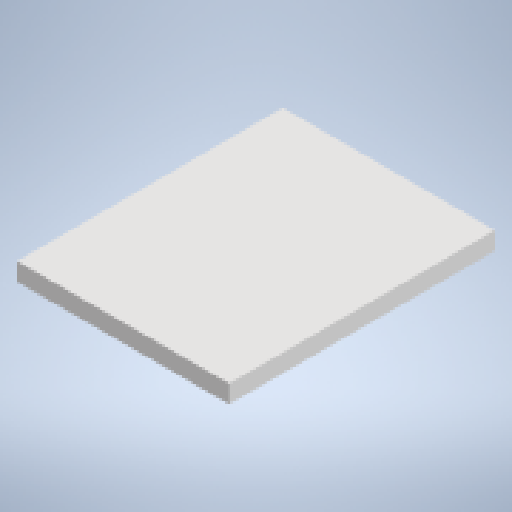
# Autodesk Inventor part: body
Saved by Autodesk Inventor 2024 (Build 280153000, 153)
## iProperties
Created: 2025-10-19
Part Number: body
Material: Generic
Document SubType Name: Modeling
Designer: indie
Density: 1 g/cm^3
Appearance: Default
Author: indie
Autodesk Inventor part; units mm, degrees
ref_plane "YZ Plane" through (0, 0, 0) normal (1, 0, 0) x (0, 1, 0)
ref_plane "XZ Plane" through (0, 0, 0) normal (0, 1, 0) x (-1, 0, 0)
ref_plane "XY Plane" through (0, 0, 0) normal (0, 0, 1) x (1, 0, 0)
sketch "Sketch1" plane through (0, 0, 0) normal (0, 1, 0) x (-1, 0, 0)
  line L0 (-190.5, 254) -> (190.5, 254)
  line L1 (190.5, 254) -> (190.5, -254)
  line L2 (190.5, -254) -> (-190.5, -254)
  line L3 (-190.5, -254) -> (-190.5, 254)
  line L4 (-190.5, 254) -> (190.5, -254) construction
  line L5 (190.5, 254) -> (-190.5, -254) construction
  point P0 (0, 0)
  dimension "d2" = 381
  dimension "d3" = 508
  constraints: 12 end point, 2 midpoint, 2 parallel, 1 horizontal, 1 perpendicular
  measures "d2" distance of L0.start L0.end
  measures "d3" distance of L2.end L0.start
extrude "Extrusion1" add sketch "Sketch1" along normal blind 25.4
sketch "Sketch2" plane through (0, 25.4, 0) normal (0, 1, 0) x (1, 0, 0)
  line L0 (19.05, 196.85) -> (-19.05, 196.85)
  line L1 (-19.05, 196.85) -> (-19.05, 234.95)
  line L2 (-19.05, 234.95) -> (19.05, 234.95)
  line L3 (19.05, 234.95) -> (19.05, 196.85)
  line L4 (19.05, 196.85) -> (-19.05, 234.95) construction
  line L5 (-19.05, 196.85) -> (19.05, 234.95) construction
  point P0 (0, 0)
  point P1 (0, 215.9)
  dimension "d4" = 38.1
  dimension "d5" = 38.1
  constraints: 12 end point, 2 midpoint, 2 parallel, 1 horizontal, 1 perpendicular
  measures "d4" distance of L1.end L2.end
  measures "d5" distance of L0.end L1.end
extrude "Extrusion2" add sketch "Sketch2" along normal blind 381
sketch "Sketch3" plane through (-19.05, 25.4, -196.85) normal (0, 0, 1) x (1, 0, 0)
  line L0 (38.1, 381) -> (0, 381) projected
  line L1 (0, 342.9) -> (38.1, 342.9)
  line L2 (38.1, 342.9) -> (38.1, 381)
  line L3 (38.1, 381) -> (0, 381)
  line L4 (0, 381) -> (0, 342.9)
  line L5 (0, 342.9) -> (38.1, 381) construction
  line L6 (38.1, 342.9) -> (0, 381) construction
  point P0 (19.05, -25.4)
  point P1 (19.05, 361.95)
  dimension "d8" = 38.1
  dimension "d9" = 38.1
  constraints: 12 end point, 2 midpoint, 2 parallel, 1 horizontal, 1 perpendicular
  measures "d8" distance of L0.start L0.end
  measures "d9" distance of L1.end L0.start
extrude "Extrusion3" add sketch "Sketch3" along normal blind 263.525
sketch "Sketch4" plane through (0, 25.4, 0) normal (0, 1, 0) x (1, 0, 0)
  line L0 (-34.925, -238.125) -> (-47.625, -238.125)
  line L1 (-47.625, -238.125) -> (-47.625, -184.15)
  line L2 (-47.625, -184.15) -> (-34.925, -184.15)
  line L3 (-34.925, -184.15) -> (-34.925, -238.125)
  line L4 (-34.925, -238.125) -> (-47.625, -184.15) construction
  line L5 (-47.625, -238.125) -> (-34.925, -184.15) construction
  line L6 (33.3375, -238.125) -> (20.6375, -238.125)
  line L7 (20.6375, -238.125) -> (20.6375, -184.15)
  line L8 (20.6375, -184.15) -> (33.3375, -184.15)
  line L9 (33.3375, -184.15) -> (33.3375, -238.125)
  line L10 (33.3375, -238.125) -> (20.6375, -184.15) construction
  line L11 (20.6375, -238.125) -> (33.3375, -184.15) construction
  line L12 (-34.925, 36.5125) -> (-47.625, 36.5125)
  line L13 (-47.625, 36.5125) -> (-47.625, 90.4875)
  line L14 (-47.625, 90.4875) -> (-34.925, 90.4875)
  line L15 (-34.925, 90.4875) -> (-34.925, 36.5125)
  line L16 (-34.925, 36.5125) -> (-47.625, 90.4875) construction
  line L17 (-47.625, 36.5125) -> (-34.925, 90.4875) construction
  line L18 (33.3375, 36.5125) -> (20.6375, 36.5125)
  line L19 (20.6375, 36.5125) -> (20.6375, 90.4875)
  line L20 (20.6375, 90.4875) -> (33.3375, 90.4875)
  line L21 (33.3375, 90.4875) -> (33.3375, 36.5125)
  line L22 (33.3375, 36.5125) -> (20.6375, 90.4875) construction
  line L23 (20.6375, 36.5125) -> (33.3375, 90.4875) construction
  point P0 (0, 0)
  point P1 (-41.275, -211.1375)
  point P2 (26.9875, -211.1375)
  point P3 (-41.275, 63.5)
  point P4 (26.9875, 63.5)
  constraints: 48 end point, 8 midpoint, 8 parallel, 4 horizontal, 4 perpendicular
extrude "Extrusion4" add sketch "Sketch4" along normal blind 50.8
sketch "Sketch5" plane through (-34.925, 25.4, 238.125) normal (1, 0, 0) x (0, 0, -1)
  circle A0 centre (26.9875, 25.4) radius 25.4
  circle A1 centre (301.625, 25.4) radius 25.4
  point P0 (238.125, -25.4)
  dimension "d14" = 50.8
  dimension "d15" = 50.8
  constraints: 2 centre point
  measures "d14" diameter of A0
  measures "d15" diameter of A1
extrude "Extrusion5" add sketch "Sketch5" along normal blind 55.5625
sketch "Sketch7" plane through (0, 76.2, 0) normal (0, 1, 0) x (1, 0, 0)
  line L0 (-34.925, 63.5) -> (-34.925, 38.1) projected
  line L1 (20.6375, -211.1375) -> (20.6375, -238.125) projected
  line L2 (-34.925, 63.5) -> (20.6375, 63.5)
  line L3 (20.6375, 63.5) -> (20.6375, -217.4875)
  line L4 (20.6375, -217.4875) -> (-34.925, -217.4875)
  line L5 (-34.925, -217.4875) -> (-34.925, 63.5)
  point P0 (0, 0)
  constraints: 8 end point, 2 parallel, 1 horizontal, 1 perpendicular, 1 point on line
extrude "Extrusion6" add sketch "Sketch7" along normal blind 3.175
body "Solid1"
